NutOld (Autodesk Fusion 360 design; units mm, degrees)
Autodesk Fusion 360 part; units mm, degrees
sketch "Sketch1" plane through (0, 0, 0) normal (0, 1, 0) x (1, 0, 0) in component "Component"
  circle A0 centre (0, 0) radius 1.25
  line L0 (0.866, -1.5) -> (1.7321, 0)
  line L1 (1.7321, 0) -> (0.866, 1.5)
  line L2 (0.866, 1.5) -> (-0.866, 1.5)
  line L3 (-0.866, 1.5) -> (-1.7321, 0)
  line L4 (-1.7321, 0) -> (-0.866, -1.5)
  line L5 (-0.866, -1.5) -> (0.866, -1.5)
  dimension "d1" = 2.5
  constraint coincident A0.centre origin
  measures "d1" diameter of A0
extrude "Extrude1" add sketch "Sketch1" along normal blind 1 in component "Component"
thread "Thread1" "ISO Metric profile 2.5 M2.5x0.45 6H" major diameter 2.58 minor diameter 2.0755 pitch 0.45 angle 60 modelled right hand crest width 0.0563 on face at (1.2484, 0.6667, 0.0623) crest through (1.0377, -0.2531, 0) in component "Component"
chamfer "Chamfer1" distance 0.05 angle 45 12 edges at (0, 1, -1.5) (1.299, 1, -0.75) (1.299, 1, 0.75) (0, 1, 1.5) (-1.299, 1, 0.75) (-1.299, 1, -0.75) (-1.299, 0, -0.75) (-1.299, 0, 0.75) (0, 0, 1.5) (1.299, 0, 0.75) (1.299, 0, -0.75) (0, 0, -1.5) tangent chain off in component "Component"
component "Component" placed x (1, 0, 0) y (0, 1, 0) z (0, 0, 1) at (0, 0, 0)
